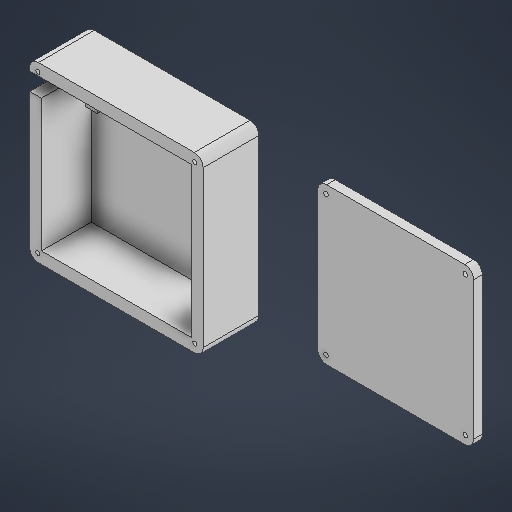
# Autodesk Inventor part: 电池包
Saved by Autodesk Inventor 2025 (Build 290162000, 162)
## iProperties
Created: 2025-09-16
Part Number: 电池包
Material: 常规
Document SubType Name: Modeling
Designer: HZD
Density: 1 g/cm^3
Appearance: 默认
Author: HZD
Autodesk Inventor part; units mm, degrees
ref_plane "YZ Plane" through (0, 0, 0) normal (1, 0, 0) x (0, 1, 0)
ref_plane "XZ Plane" through (0, 0, 0) normal (0, 1, 0) x (-1, 0, 0)
ref_plane "XY Plane" through (0, 0, 0) normal (0, 0, 1) x (1, 0, 0)
sketch "草图1" plane through (0, 0, 0) normal (0, 0, 1) x (1, 0, 0)
  line L0 (25.5, -25.5) -> (-25.5, -25.5)
  line L1 (-25.5, -25.5) -> (-25.5, 25.5)
  line L2 (-25.5, 25.5) -> (25.5, 25.5)
  line L3 (25.5, 25.5) -> (25.5, -25.5)
  line L4 (25.5, -25.5) -> (-25.5, 25.5) construction
  line L5 (-25.5, -25.5) -> (25.5, 25.5) construction
  line L6 (29.5, -29.5) -> (-29.5, -29.5)
  line L7 (-29.5, -29.5) -> (-29.5, 29.5)
  line L8 (-29.5, 29.5) -> (29.5, 29.5)
  line L9 (29.5, 29.5) -> (29.5, -29.5)
  point P0 (0, 0)
  dimension "d0" = 51
  dimension "d1" = 51
  dimension "d4" = 4
  constraints: 20 end point, 4 parallel, 2 midpoint, 2 perpendicular, 1 horizontal, 3 other
  measures "d0" distance of L2.end L0.start
  measures "d1" distance of L1.end L2.end
  measures "d4" distance between parallel lines of L3 L9
extrude "拉伸1" add sketch "草图1" along normal blind 17
sketch "草图2" plane through (0, 0, 0) normal (0, 0, -1) x (-1, 0, 0)
  line L0 (-29.5, 29.5) -> (29.5, 29.5) projected
  line L1 (-29.5, -29.5) -> (-29.5, 29.5) projected
  line L2 (29.5, -29.5) -> (-29.5, -29.5) projected
  line L3 (29.5, 29.5) -> (29.5, -29.5) projected
  line L4 (-25.5, -25.5) -> (25.5, -25.5) projected
  line L5 (-25.5, 25.5) -> (-25.5, -25.5) projected
  line L6 (25.5, 25.5) -> (-25.5, 25.5) projected
  line L7 (25.5, -25.5) -> (25.5, 25.5) projected
  point P0 (0, 0)
extrude "拉伸2" add sketch "草图2" along normal blind 2 contours L0 L3 L2 L1 | L5 L6 L7 L4
fillet "圆角1" radius 3 4 edges at (-29.5, 29.5, 7.5) (-29.5, -29.5, 7.5) (29.5, -29.5, 7.5) (29.5, 29.5, 7.5)
sketch "草图3" plane through (0, 0, 0) normal (0, 0, 1) x (1, 0, 0)
  line L0 (-10.5, 20.5) -> (-14.5, 20.5)
  line L1 (-14.5, 20.5) -> (-14.5, 25.5)
  line L2 (-14.5, 25.5) -> (-10.5, 25.5)
  line L3 (-10.5, 25.5) -> (-10.5, 20.5)
  line L4 (-10.5, 20.5) -> (-14.5, 25.5) construction
  line L5 (-14.5, 20.5) -> (-10.5, 25.5) construction
  line L6 (-25.5, -25.5) -> (-25.5, 25.5) projected
  point P0 (0, 0)
  point P1 (-12.5, 23)
  dimension "d8" = 11
  dimension "d9" = 4
  dimension "d10" = 5
  constraints: 12 end point, 2 midpoint, 2 parallel, 1 horizontal, 1 perpendicular
  measures "d8" distance between parallel lines of L6 L1
  measures "d9" distance of L1.end L2.end
  measures "d10" distance of L0.end L1.end
extrude "拉伸3" add sketch "草图3" along normal blind 13
sketch "草图4" plane through (-14.5, 20.5, 0) normal (0, -1, 0) x (1, 0, 0)
  point P0 (14.5, 0)
sketch "草图5" plane through (-14.5, 20.5, 0) normal (0, -1, 0) x (1, 0, 0)
  line L0 (0, 0) -> (0, 13) projected
  line L1 (4, 0) -> (4, 13) projected
  line L2 (0, 4) -> (4, 4)
  line L3 (4, 0) -> (40, 0) projected
  line L4 (4, 0) -> (0, 0) projected
  point P0 (14.5, 0)
  dimension "d13" = 4
  constraints: 2 end point, 2 point on line, 1 perpendicular
  measures "d13" distance between parallel lines of L2 L3
extrude "拉伸4" cut sketch "草图5" against normal up to surface (5 mm away)
fillet "圆角2" radius 2 1 edges at (-10.5, 25.5, 8.5)
sketch "草图6" plane through (-25.5, -25.5, 17) normal (1, 0, 0) x (0, 0, -1)
  line L0 (17, 0) -> (17, 51) projected
  line L1 (17, 51) -> (0, 51) projected
  line L2 (0, 0) -> (0, 51) projected
  line L3 (17, 0) -> (0, 0) projected
  line L4 (0, 52) -> (0, -1) projected
  line L5 (0, 45) -> (17, 45)
  point P0 (17, 25.5)
  dimension "d17" = 6
  constraints: 2 end point, 2 point on line, 1 perpendicular
  measures "d17" distance between parallel lines of L1 L5
extrude "拉伸5" cut sketch "草图6" against normal blind 13 contours L5 L2 L1 L0
sketch "草图7" plane through (0, 0, -2) normal (0, 0, -1) x (-1, 0, 0)
  point P0 (0, 0)
sketch "草图8" plane through (0, 0, 17) normal (0, 0, 1) x (1, 0, 0)
  circle A0 centre (26.7, 26.7) radius 0.7
  arc A1 (29.5, 26.5) -> (26.5, 29.5) centre (26.5, 26.5) ccw projected
  line L0 (-29.5, -26.5) -> (-29.5, 26.5) projected
  line L1 (-29.5, 0) -> (29.5, 0)
  line L2 (26.5, 29.5) -> (-26.5, 29.5) projected
  line L3 (0, 29.5) -> (0, -29.4831)
  circle A2 centre (26.7, -26.7) radius 0.7
  circle A3 centre (-26.7, 26.7) radius 0.7
  circle A4 centre (-26.7, -26.7) radius 0.7
  line L4 (29.5, -26.5) -> (29.5, 26.5) projected
  point P0 (0, 0)
  dimension "d20" = 1.4
  dimension "d28" = 2.8
  dimension "d29" = 2.8
  constraints: 4 centre point, 4 end point, 3 symmetric about line, 2 midpoint, 1 horizontal, 1 vertical, 3 other
  measures "d20" diameter of A0
  measures "d28" distance from line of A0.centre L2
  measures "d29" distance from line of A0.centre L4
extrude "拉伸6" cut sketch "草图8" against normal blind 8 contours A0 | A2 | A3 | A4
sketch "草图9" plane through (0, 0, -2) normal (0, 0, -1) x (-1, 0, 0)
  line L0 (-105.5055, 26.5) -> (-52.5055, 26.5)
  line L1 (-52.5055, 26.5) -> (-52.5055, -26.5)
  line L2 (-52.5055, -26.5) -> (-105.5055, -26.5)
  line L3 (-105.5055, -26.5) -> (-105.5055, 26.5)
  line L4 (-105.5055, 26.5) -> (-52.5055, -26.5) construction
  line L5 (-52.5055, 26.5) -> (-105.5055, -26.5) construction
  point P0 (0, 0)
  point P1 (-79.0055, 0)
  dimension "d23" = 53
  dimension "d24" = 53
  constraints: 12 end point, 2 midpoint, 2 parallel, 1 horizontal, 1 perpendicular
  measures "d23" distance of L1.end L2.end
  measures "d24" distance of L2.end L0.start
extrude "拉伸7" add sketch "草图9" against normal blind 3
fillet "圆角3" radius 3 4 edges at (52.5055, -26.5, -0.5) (105.5055, -26.5, -0.5) (105.5055, 26.5, -0.5) (52.5055, 26.5, -0.5)
sketch "草图10" plane through (0, 0, 1) normal (0, 0, 1) x (1, 0, 0)
  circle A0 centre (55.3055, 23.7) radius 0.75
  line L0 (102.5055, 26.5) -> (55.5055, 26.5) projected
  line L1 (52.5055, 23.5) -> (52.5055, -23.5) projected
  line L2 (52.5055, 0) -> (105.5055, 0)
  line L3 (105.5055, 23.5) -> (105.5055, -23.5) projected
  line L4 (79.0055, 26.5) -> (79.0055, -26.5)
  line L5 (102.5055, -26.5) -> (55.5055, -26.5) projected
  circle A1 centre (102.7055, 23.7) radius 0.75
  circle A2 centre (55.3055, -23.7) radius 0.75
  circle A3 centre (102.7055, -23.7) radius 0.75
  point P0 (0, 0)
  dimension "d30" = 1.5
  dimension "d31" = 2.8
  dimension "d32" = 2.8
  constraints: 4 centre point, 4 end point, 4 midpoint, 3 symmetric about line, 3 other
  measures "d30" diameter of A0
  measures "d31" distance from line of A0.centre L0
  measures "d32" distance from line of A0.centre L1
extrude "拉伸8" cut sketch "草图10" against normal blind 3
